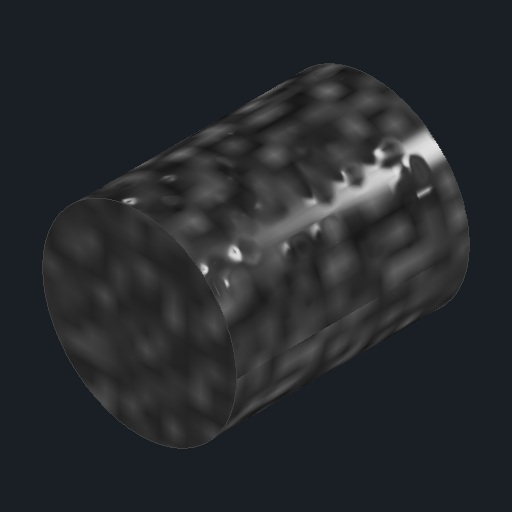
# Autodesk Inventor part: m5_grub_6
Saved by Autodesk Inventor 2027.1 (Build 311270010, 270A)
## iProperties
Created: 2026-11-04
Part Number: m5_grub_6
Material: Generic
Description: M5x6 grub screw: worm carrier push screw (mesh adjust)
Document SubType Name: Modeling
Designer: Claude (from photos)
Density: 1 g/cm^3
Appearance: Black Cast
Author: alexg
Autodesk Inventor part; units mm, degrees
ref_plane "YZ Plane" through (0, 0, 0) normal (1, 0, 0) x (0, 1, 0)
ref_plane "XZ Plane" through (0, 0, 0) normal (0, 1, 0) x (-1, 0, 0)
ref_plane "XY Plane" through (0, 0, 0) normal (0, 0, 1) x (1, 0, 0)
sketch "Grub M5x6 sketch" plane through (0, 0, 0) normal (0, 0, 1) x (1, 0, 0)
  circle A0 centre (0, 0) radius 2.5
  constraints: 1 centre point
extrude "Grub M5x6" add sketch "Grub M5x6 sketch" along normal blind 6
sketch "Hex socket 2.5 sketch" plane through (0, 0, 0) normal (0, 0, 1) x (1, 0, 0)
  line L0 (1.4434, 0) -> (0.7217, 1.25)
  line L1 (0.7217, 1.25) -> (-0.7217, 1.25)
  line L2 (-0.7217, 1.25) -> (-1.4434, 0)
  line L3 (-1.4434, 0) -> (-0.7217, -1.25)
  line L4 (-0.7217, -1.25) -> (0.7217, -1.25)
  line L5 (0.7217, -1.25) -> (1.4434, 0)
  constraints: 12 end point
extrude "Hex socket 2.5" cut sketch "Hex socket 2.5 sketch" along normal blind 2.5
body "Solid1"
